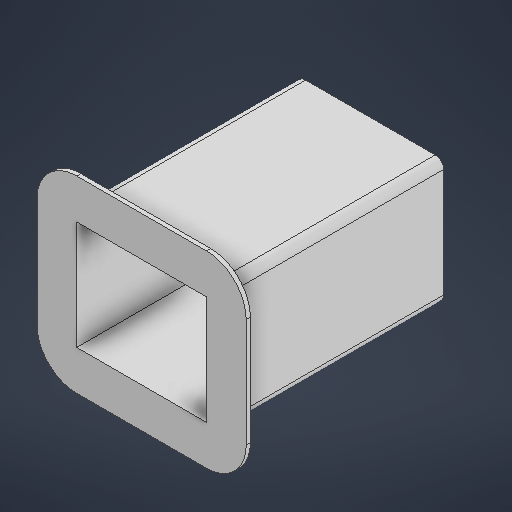
# Autodesk Inventor part: 01_Base_original_MG90S_CPY1
Saved by Autodesk Inventor 2027.2 (Build 312334000, 334)
## iProperties
Created: 2026-09-17
Part Number: 01_Base_original_MG90S_CPY1
Project: STAR TRACKER
Material: Genérico
Document SubType Name: Modeling
Designer: alexa
Mass: 103.85 g
Surface Area: 635.702 cm^2
Volume: 103.85 cm^3
Density: 1 g/cm^3
Appearance: Valor por defecto
Title: Base
Author: alexa
Autodesk Inventor part; units mm, degrees
sketch "Boceto1" plane through (0, 0, 0) normal (0, 0, 1) x (1, 0, 0)
  line L0 (-35, 30) -> (35, 30)
  line L1 (35, 30) -> (35, -30)
  line L2 (35, -30) -> (-35, -30)
  line L3 (-35, -30) -> (-35, 30)
  point P0 (0, 0)
  point P1 (-35, 0)
  point P2 (0, -30)
  dimension "d0" = 70
  dimension "d1" = 60
  constraints: 8 end point, 2 midpoint, 2 parallel, 1 horizontal, 1 horizontal alignment, 1 perpendicular, 1 vertical alignment
  measures "d0" distance of L1.end L2.end
  measures "d1" distance of L0.end L1.end
extrude "Extrusión1" add sketch "Boceto1" along normal blind 2
sketch "Boceto3" plane through (0, 0, 2) normal (0, 0, 1) x (1, 0, 0)
  line L0 (-35, -30) -> (35, -30) projected
  line L1 (35, -30) -> (35, 30) projected
  line L2 (35, 30) -> (-35, 30) projected
  line L3 (-35, 30) -> (-35, -30) projected
  line L4 (-33, -28) -> (33, -28)
  line L5 (33, -28) -> (33, 28)
  line L6 (33, 28) -> (-33, 28)
  line L7 (-33, 28) -> (-33, -28)
  point P0 (0, 0)
  dimension "d13" = 2
  constraints: 8 end point, 3 other
  measures "d13" distance between parallel lines of L3 L7
extrude "Extrusión3" add sketch "Boceto3" along normal blind 211.5
sketch "Boceto4" plane through (0, 0, 0) normal (0, 0, -1) x (-1, 0, 0)
  arc A0 (19.55, -10) -> (20.15, -9.4) centre (19.55, -9.4) ccw projected
  line L0 (20.15, -3.4117) -> (20.15, -9.4) projected
  line L1 (20.15, 0) -> (20.15, -3.4117) projected
  line L2 (20.15, 3.4117) -> (20.15, 0) projected
  line L3 (20.15, 9.4) -> (20.15, 3.4117) projected
  arc A1 (20.15, 9.4) -> (19.55, 10) centre (19.55, 9.4) ccw projected
  line L4 (10.15, 10) -> (19.55, 10) projected
  line L5 (-13.9922, 10) -> (10.15, 10) projected
  line L6 (-19.55, 10) -> (-13.9922, 10) projected
  arc A2 (-19.55, 10) -> (-20.15, 9.4) centre (-19.55, 9.4) ccw projected
  line L7 (-20.15, -9.4) -> (-20.15, 9.4) projected
  arc A3 (-20.15, -9.4) -> (-19.55, -10) centre (-19.55, -9.4) ccw projected
  line L8 (-13.9922, -10) -> (-19.55, -10) projected
  line L9 (10.15, -10) -> (-13.9922, -10) projected
  line L10 (19.55, -10) -> (10.15, -10) projected
  arc A4 (26.2, -2.544) -> (26.2, -6.456) centre (25.15, -4.5) ccw projected
  arc A5 (26.2, 6.456) -> (26.2, 2.544) centre (25.15, 4.5) ccw projected
  arc A6 (-26.2, 2.544) -> (-26.2, 6.456) centre (-25.15, 4.5) ccw projected
  arc A7 (-26.2, -6.456) -> (-26.2, -2.544) centre (-25.15, -4.5) ccw projected
  line L11 (-13.9922, -10.5) -> (-19.55, -10.5)
  arc A8 (-20.65, -9.4) -> (-19.55, -10.5) centre (-19.55, -9.4) ccw
  line L12 (-20.65, -9.4) -> (-20.65, 9.4)
  arc A9 (-19.55, 10.5) -> (-20.65, 9.4) centre (-19.55, 9.4) ccw
  line L13 (-19.55, 10.5) -> (-13.9922, 10.5)
  line L14 (-13.9922, 10.5) -> (10.15, 10.5)
  line L15 (10.15, 10.5) -> (19.55, 10.5)
  arc A10 (20.65, 9.4) -> (19.55, 10.5) centre (19.55, 9.4) ccw
  line L16 (20.65, 9.4) -> (20.65, 3.4117)
  line L17 (20.65, 3.4117) -> (20.65, 0)
  line L18 (20.65, 0) -> (20.65, -3.4117)
  line L19 (20.65, -3.4117) -> (20.65, -9.4)
  arc A11 (19.55, -10.5) -> (20.65, -9.4) centre (19.55, -9.4) ccw
  line L20 (19.55, -10.5) -> (10.15, -10.5)
  line L21 (10.15, -10.5) -> (-13.9922, -10.5)
  circle A12 centre (25.15, -4.5) radius 2
  circle A13 centre (25.15, 4.5) radius 2
  circle A14 centre (-25.15, -4.5) radius 2
  circle A15 centre (-25.15, 4.5) radius 2
  point P0 (0, 0)
  dimension "d16" = 0.5
  dimension "d17" = 4
  dimension "d18" = 4
  dimension "d19" = 4
  dimension "d20" = 4
  constraints: 22 end point, 8 centre point, 8 point on circle, 4 coincident, 14 other
  measures "d16" distance between parallel lines of L9 L21
  measures "d17" diameter of A12
  measures "d18" diameter of A13
  measures "d19" diameter of A14
  measures "d20" diameter of A15
extrude "Extrusión4" cut sketch "Boceto4" against normal blind 40 contours L10 L9 L8 A3 L7 A2 L6 L5 L4 A1 L3 L2 L1 L0 A0 | L11 A8 L12 A9 L13 L14 L15 A10 L16 L17 L18 L19 A11 L20 L21 | A12 | A13 | A14 | A15
fillet "Empalme1" radius 4 4 edges at (-35, -30, 106.75) (35, -30, 106.75) (-35, 30, 106.75) (35, 30, 106.75)
sketch "Boceto5" plane through (0, 0, 213.5) normal (0, 0, 1) x (1, 0, 0)
  arc A0 (35, 26) -> (31, 30) centre (31, 26) ccw projected
  line L0 (31, 30) -> (-31, 30) projected
  arc A1 (-31, 30) -> (-35, 26) centre (-31, 26) ccw projected
  line L1 (-35, 26) -> (-35, -26) projected
  arc A2 (-35, -26) -> (-31, -30) centre (-31, -26) ccw projected
  line L2 (-31, -30) -> (31, -30) projected
  arc A3 (31, -30) -> (35, -26) centre (31, -26) ccw projected
  line L3 (35, -26) -> (35, 26) projected
  line L4 (-33, -28) -> (-33, 28) projected
  line L5 (-33, 28) -> (33, 28) projected
  line L6 (33, 28) -> (33, -28) projected
  line L7 (33, -28) -> (-33, -28) projected
  line L8 (31, -45) -> (-31, -45)
  arc A4 (-50, -26) -> (-31, -45) centre (-31, -26) ccw
  line L9 (-50, -26) -> (-50, 26)
  arc A5 (-31, 45) -> (-50, 26) centre (-31, 26) ccw
  line L10 (-31, 45) -> (31, 45)
  arc A6 (50, 26) -> (31, 45) centre (31, 26) ccw
  line L11 (50, 26) -> (50, -26)
  arc A7 (31, -45) -> (50, -26) centre (31, -26) ccw
  point P0 (0, 0)
  dimension "d24" = 15
  constraints: 8 end point, 8 point on circle, 4 centre point, 7 other
  measures "d24" distance between parallel lines of L2 L8
extrude "Extrusión5" add sketch "Boceto5" against normal blind 2 contours L8 A4 L9 A5 L10 A6 L11 A7
chamfer "Chaflán1" distance 4 angle 45 4 edges at (-33.8284, 28.8284, 211.5) (33.8284, 28.8284, 211.5) (33.8284, -28.8284, 211.5) (-33.8284, -28.8284, 211.5)
sketch "Cerrar_montaje_MG996R_perfil" plane through (0, 0, 0) normal (0, 0, 1) x (1, 0, 0)
  line L0 (-30, -14) -> (30, -14)
  line L1 (30, -14) -> (30, 14)
  line L2 (30, 14) -> (-30, 14)
  line L3 (-30, 14) -> (-30, -14)
  constraints: 8 end point
extrude "Cerrar_montaje_MG996R" add sketch "Cerrar_montaje_MG996R_perfil" along normal blind 2
ref_plane "Plano de trabajo1" through (0, 0, -4.6) normal (0, 0, 1) x (1, 0, 0)
sketch "Asiento_MG90S_integrado_perfil" plane through (0, 0, -4.6) normal (0, 0, 1) x (1, 0, 0)
  line L0 (-24, -11) -> (15, -11)
  line L1 (15, -11) -> (15, 11)
  line L2 (15, 11) -> (-24, 11)
  line L3 (-24, 11) -> (-24, -11)
  constraints: 8 end point
extrude "Asiento_MG90S_integrado" add sketch "Asiento_MG90S_integrado_perfil" along normal blind 4.6
ref_plane "Plano de trabajo2" through (0, 0, -4.7) normal (0, 0, 1) x (1, 0, 0)
sketch "Paso_cuerpo_MG90S_perfil" plane through (0, 0, -4.7) normal (0, 0, 1) x (1, 0, 0)
  line L0 (-16.45, -6.5) -> (7.05, -6.5)
  line L1 (7.05, -6.5) -> (7.05, 6.5)
  line L2 (7.05, 6.5) -> (-16.45, 6.5)
  line L3 (-16.45, 6.5) -> (-16.45, -6.5)
  constraints: 8 end point
extrude "Paso_cuerpo_MG90S" cut sketch "Paso_cuerpo_MG90S_perfil" along normal blind 6.8
ref_plane "Plano de trabajo3" through (0, 0, -4.7) normal (0, 0, 1) x (1, 0, 0)
sketch "Paso_M2_9.35_perfil" plane through (0, 0, -4.7) normal (0, 0, 1) x (1, 0, 0)
  circle A0 centre (9.35, 0) radius 1.1
  constraints: 1 centre point
extrude "Paso_M2_9.35" cut sketch "Paso_M2_9.35_perfil" along normal blind 6.8
ref_plane "Plano de trabajo4" through (0, 0, -2.8) normal (0, 0, 1) x (1, 0, 0)
sketch "Tuerca_M2_9.35_perfil" plane through (0, 0, -2.8) normal (0, 0, 1) x (1, 0, 0)
  line L0 (11.7749, 0) -> (10.5624, 2.1)
  line L1 (10.5624, 2.1) -> (8.1376, 2.1)
  line L2 (8.1376, 2.1) -> (6.9251, 0)
  line L3 (6.9251, 0) -> (8.1376, -2.1)
  line L4 (8.1376, -2.1) -> (10.5624, -2.1)
  line L5 (10.5624, -2.1) -> (11.7749, 0)
  constraints: 12 end point
extrude "Tuerca_M2_9.35" cut sketch "Tuerca_M2_9.35_perfil" along normal blind 1.8
ref_plane "Plano de trabajo5" through (0, 0, -2.8) normal (0, 0, 1) x (1, 0, 0)
sketch "Entrada_lateral_tuerca_9.35_perfil" plane through (0, 0, -2.8) normal (0, 0, 1) x (1, 0, 0)
  line L0 (6.85, 0) -> (11.85, 0)
  line L1 (11.85, 0) -> (11.85, 11.1)
  line L2 (11.85, 11.1) -> (6.85, 11.1)
  line L3 (6.85, 11.1) -> (6.85, 0)
  constraints: 8 end point
extrude "Entrada_lateral_tuerca_9.35" cut sketch "Entrada_lateral_tuerca_9.35_perfil" along normal blind 1.8
ref_plane "Plano de trabajo6" through (0, 0, -4.7) normal (0, 0, 1) x (1, 0, 0)
sketch "Paso_M2_-18.65_perfil" plane through (0, 0, -4.7) normal (0, 0, 1) x (1, 0, 0)
  circle A0 centre (-18.65, 0) radius 1.1
  constraints: 1 centre point
extrude "Paso_M2_-18.65" cut sketch "Paso_M2_-18.65_perfil" along normal blind 6.8
ref_plane "Plano de trabajo7" through (0, 0, -2.8) normal (0, 0, 1) x (1, 0, 0)
sketch "Tuerca_M2_-18.65_perfil" plane through (0, 0, -2.8) normal (0, 0, 1) x (1, 0, 0)
  line L0 (-16.2251, 0) -> (-17.4376, 2.1)
  line L1 (-17.4376, 2.1) -> (-19.8624, 2.1)
  line L2 (-19.8624, 2.1) -> (-21.0749, 0)
  line L3 (-21.0749, 0) -> (-19.8624, -2.1)
  line L4 (-19.8624, -2.1) -> (-17.4376, -2.1)
  line L5 (-17.4376, -2.1) -> (-16.2251, 0)
  constraints: 12 end point
extrude "Tuerca_M2_-18.65" cut sketch "Tuerca_M2_-18.65_perfil" along normal blind 1.8
ref_plane "Plano de trabajo8" through (0, 0, -2.8) normal (0, 0, 1) x (1, 0, 0)
sketch "Entrada_lateral_tuerca_-18.65_perfil" plane through (0, 0, -2.8) normal (0, 0, 1) x (1, 0, 0)
  line L0 (-21.15, 0) -> (-16.15, 0)
  line L1 (-16.15, 0) -> (-16.15, 11.1)
  line L2 (-16.15, 11.1) -> (-21.15, 11.1)
  line L3 (-21.15, 11.1) -> (-21.15, 0)
  constraints: 8 end point
extrude "Entrada_lateral_tuerca_-18.65" cut sketch "Entrada_lateral_tuerca_-18.65_perfil" along normal blind 1.8
ref_plane "Yaw_plano_axial" through (-10.15, 0, -72.5) normal (0, 0, -1) x (0, -1, 0)
ref_plane "Yaw_cero" through (-10.15, 0, -72.5) normal (0, -1, 0) x (0, 0, -1)
ref_plane "Servo_yaw_ref_1" through (-10.15, 0, -4.6) normal (-1, 0, 0) x (0, 1, 0)
ref_plane "Servo_yaw_ref_2" through (-10.15, 0, -4.6) normal (0, 1, 0) x (1, 0, 0)
ref_plane "Servo_yaw_ref_3" through (-10.15, 0, -4.6) normal (0, 0, -1) x (1, 0, 0)
ref_plane "M2_motor_yaw_0_ref_1" through (9.35, 0, -2.7) normal (1, 0, 0) x (0, 1, 0)
ref_plane "M2_motor_yaw_0_ref_2" through (9.35, 0, -2.7) normal (0, 1, 0) x (1, 0, 0)
ref_plane "M2_motor_yaw_0_ref_3" through (9.35, 0, -2.7) normal (0, 0, 1) x (1, 0, 0)
ref_plane "M2_motor_yaw_1_ref_1" through (-18.65, 0, -2.7) normal (1, 0, 0) x (0, 1, 0)
ref_plane "M2_motor_yaw_1_ref_2" through (-18.65, 0, -2.7) normal (0, 1, 0) x (1, 0, 0)
ref_plane "M2_motor_yaw_1_ref_3" through (-18.65, 0, -2.7) normal (0, 0, 1) x (1, 0, 0)
sketch "Boceto15" plane through (0, 0, 0) normal (0, 0, -1) x (-1, 0, 0)
  line L0 (24, 11) -> (24, -11) projected
  line L1 (24, -11) -> (-15, -11) projected
  line L2 (-15, -11) -> (-15, 11) projected
  line L3 (-15, 11) -> (24, 11) projected
  arc A0 (-31, 30) -> (-35, 26) centre (-31, 26) ccw projected
  line L4 (-35, -26) -> (-35, 26) projected
  arc A1 (-35, -26) -> (-31, -30) centre (-31, -26) ccw projected
  line L5 (31, -30) -> (-31, -30) projected
  arc A2 (31, -30) -> (35, -26) centre (31, -26) ccw projected
  line L6 (35, 26) -> (35, -26) projected
  arc A3 (35, 26) -> (31, 30) centre (31, 26) ccw projected
  line L7 (-31, 30) -> (31, 30) projected
  circle A4 centre (18.65, 0) radius 1.1 projected
  circle A5 centre (-9.35, 0) radius 1.1 projected
  line L8 (16.45, 6.5) -> (16.45, -6.5) projected
  line L9 (16.45, -6.5) -> (-7.05, -6.5) projected
  line L10 (-7.05, -6.5) -> (-7.05, 6.5) projected
  line L11 (-7.05, 6.5) -> (16.45, 6.5) projected
  line L12 (24, -11) -> (-15, -11) projected
  line L13 (24, 11) -> (24, -11) projected
  line L14 (-15, 11) -> (24, 11) projected
  line L15 (-15, -11) -> (-15, 11) projected
  point P0 (0, 0)
extrude "Extrusión15" add sketch "Boceto15" along normal blind 4.6 contours L0 L1 L2 L3 | L7 A3 L6 A2 L5 A1 L4 A0
sketch "Boceto16" plane through (0, 0, 2) normal (0, 0, 1) x (1, 0, 0)
  circle A0 centre (-18.65, 0) radius 1.1 projected
  circle A1 centre (9.35, 0) radius 1.1 projected
  line L0 (-16.45, -6.5) -> (-16.45, 6.5) projected
  line L1 (-16.45, 6.5) -> (7.05, 6.5) projected
  line L2 (7.05, 6.5) -> (7.05, -6.5) projected
  line L3 (7.05, -6.5) -> (-16.45, -6.5) projected
  line L4 (-33, -28) -> (33, -28) projected
  line L5 (33, -28) -> (33, 28) projected
  line L6 (33, 28) -> (-33, 28) projected
  line L7 (-33, 28) -> (-33, -28) projected
  point P0 (0, 0)
extrude "Extrusión16" cut sketch "Boceto16" against normal blind 3.6
sketch "Boceto17" plane through (0, 0, 213.5) normal (0, 0, 1) x (1, 0, 0)
  line L0 (-33, -28) -> (-33, 28) projected
  line L1 (-33, 28) -> (33, 28) projected
  line L2 (33, 28) -> (33, -28) projected
  line L3 (33, -28) -> (-33, -28) projected
  line L4 (-31, 26) -> (-31, -26)
  line L5 (-31, -26) -> (31, -26)
  line L6 (31, -26) -> (31, 26)
  line L7 (31, 26) -> (-31, 26)
  point P0 (0, 0)
  dimension "d60" = 2
  constraints: 8 end point, 3 other
  measures "d60" distance between parallel lines of L0 L4
extrude "Extrusión17" add sketch "Boceto17" against normal blind 215.1
ref_plane "Plano de trabajo20" through (0, 0, 104) normal (0, 0, 1) x (1, 0, 0)
sketch "Boceto18" plane through (0, 0, 104) normal (0, 0, 1) x (1, 0, 0)
  line L0 (-31, 30) -> (31, 30) projected
  arc A0 (35, 26) -> (31, 30) centre (31, 26) ccw projected
  line L1 (35, 26) -> (35, -26) projected
  arc A1 (31, -30) -> (35, -26) centre (31, -26) ccw projected
  line L2 (31, -30) -> (-31, -30) projected
  arc A2 (-35, -26) -> (-31, -30) centre (-31, -26) ccw projected
  line L3 (-35, -26) -> (-35, 26) projected
  arc A3 (-31, 30) -> (-35, 26) centre (-31, 26) ccw projected
  circle A4 centre (-18.65, 0) radius 1.1 projected
  circle A5 centre (9.35, 0) radius 1.1 projected
  line L4 (-16.45, 6.5) -> (-16.45, -6.5) projected
  line L5 (-16.45, -6.5) -> (7.05, -6.5) projected
  line L6 (7.05, -6.5) -> (7.05, 6.5) projected
  line L7 (7.05, 6.5) -> (-16.45, 6.5) projected
  line L8 (-31, 26) -> (31, 26) projected
  line L9 (31, 26) -> (31, -26) projected
  line L10 (31, -26) -> (-31, -26) projected
  line L11 (-31, -26) -> (-31, 26) projected
  line L12 (31, 45) -> (-31, 45) projected
  arc A6 (-31, 45) -> (-50, 26) centre (-31, 26) ccw projected
  line L13 (-50, 26) -> (-50, -26) projected
  arc A7 (-50, -26) -> (-31, -45) centre (-31, -26) ccw projected
  line L14 (-31, -45) -> (31, -45) projected
  arc A8 (31, -45) -> (50, -26) centre (31, -26) ccw projected
  line L15 (50, -26) -> (50, 26) projected
  arc A9 (50, 26) -> (31, 45) centre (31, 26) ccw projected
  point P0 (0, 0)
extrude "Extrusión18" cut sketch "Boceto18" against normal blind 124.75 contours L0 A0 L1 A1 L2 A2 L3 A3 | L8 L9 L10 L11
sketch "Boceto19" plane through (0, 0, 104) normal (0, 0, -1) x (-1, 0, 0)
  line L0 (-31, 26) -> (-31, -26) projected
  line L1 (31, 26) -> (-31, 26) projected
  line L2 (31, -26) -> (31, 26) projected
  line L3 (-31, -26) -> (31, -26) projected
  line L4 (31, -30) -> (-31, -30) projected
  arc A0 (31, -30) -> (35, -26) centre (31, -26) ccw projected
  line L5 (35, 26) -> (35, -26) projected
  arc A1 (35, 26) -> (31, 30) centre (31, 26) ccw projected
  line L6 (-31, 30) -> (31, 30) projected
  arc A2 (-31, 30) -> (-35, 26) centre (-31, 26) ccw projected
  line L7 (-35, -26) -> (-35, 26) projected
  arc A3 (-35, -26) -> (-31, -30) centre (-31, -26) ccw projected
  line L8 (-31, -28.15) -> (31, -28.15)
  arc A4 (31, -28.15) -> (33.15, -26) centre (31, -26) ccw
  line L9 (33.15, -26) -> (33.15, 26)
  arc A5 (33.15, 26) -> (31, 28.15) centre (31, 26) ccw
  line L10 (31, 28.15) -> (-31, 28.15)
  arc A6 (-31, 28.15) -> (-33.15, 26) centre (-31, 26) ccw
  line L11 (-33.15, 26) -> (-33.15, -26)
  arc A7 (-33.15, -26) -> (-31, -28.15) centre (-31, -26) ccw
  point P0 (0, 0)
  dimension "d66" = 1.85
  constraints: 8 end point, 8 point on circle, 4 centre point, 7 other
  measures "d66" distance between parallel lines of L4 L8
extrude "Extrusión19" cut sketch "Boceto19" against normal blind 25 contours A7 L11 A6 L10 A5 L9 A4 L8
